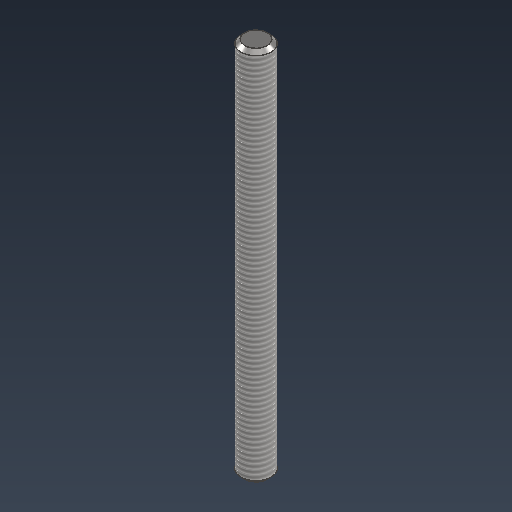
# Autodesk Inventor part: 2020 FootEnd_t8
Saved by Autodesk Inventor 2026.2 (Build 302298010, 298A)
## iProperties
Created: 2026-05-13
Part Number: 2020 FootEnd_t8
Material: 스테인리스스틸
Document SubType Name: Modeling
Designer: khw
Density: 8 g/cm^3
Appearance: 반연마
Author: khw
Autodesk Inventor part; units mm, degrees
ref_plane "YZ Plane" through (0, 0, 0) normal (1, 0, 0) x (0, 1, 0)
ref_plane "XZ Plane" through (0, 0, 0) normal (0, 1, 0) x (-1, 0, 0)
ref_plane "XY Plane" through (0, 0, 0) normal (0, 0, 1) x (1, 0, 0)
sketch "스케치1" plane through (0, 0, 0) normal (0, 1, 0) x (-1, 0, 0)
  circle A0 centre (0, 0) radius 4
  dimension "d0" = 8
  constraints: 1 centre point, 1 coincident
  measures "d0" diameter of A0
extrude "돌출1" add sketch "스케치1" along normal blind 100
thread "스레드1" size "M8x1.25" class "6g" standard "ISO Metric profile" full length
chamfer "모따기1" distance 1 angle 45 2 edges at (4, 100, 0) (4, 0, 0)
